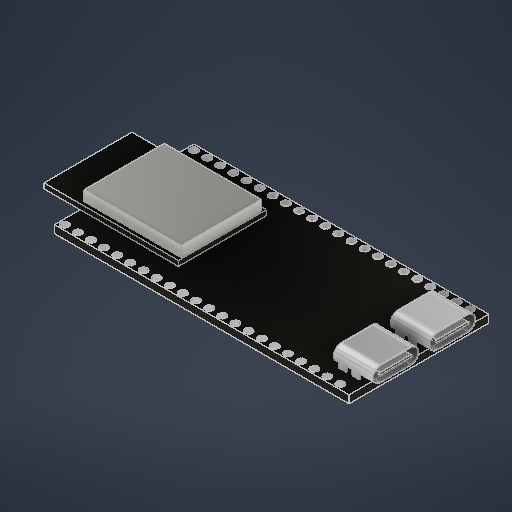
# Autodesk Inventor part: ESP32-S3
Saved by Autodesk Inventor 2027.1 (Build 311270010, 270A)
## iProperties
Created: 2026-09-22
Part Number: ESP32-S3
Material: 열가소성 수지
Document SubType Name: Modeling
Designer: khw
Density: 1.28 g/cm^3
Appearance: 매끄러움 - 검은색
Author: khw
Autodesk Inventor part; units mm, degrees
sketch "스케치1" plane through (0, 0, 0) normal (0, 1, 0) x (-1, 0, 0)
  line L0 (0, 0) -> (57, 0)
  line L1 (57, 0) -> (57, -27)
  line L2 (57, -27) -> (0, -27)
  line L3 (0, -27) -> (0, 0)
  line L4 (63, -5) -> (37, -5)
  line L5 (37, -5) -> (37, -22)
  line L6 (37, -22) -> (63, -22)
  line L7 (63, -22) -> (63, -5)
  point P0 (63, -13.5)
  point P1 (57, -13.5)
  dimension "d0" = 57
  dimension "d1" = 27
  dimension "d2" = 26
  dimension "d3" = 17
  dimension "d4" = 6
  constraints: 16 end point, 4 parallel, 2 horizontal, 2 midpoint, 2 perpendicular, 1 horizontal alignment
  measures "d0" distance of L1.end L2.end
  measures "d1" distance of L0.end L1.end
  measures "d2" distance of L6.end L5.end
  measures "d3" distance of L5.end L4.end
  measures "d4" distance of point (63, -13.5) point (57, -13.5)
extrude "돌출1" add sketch "스케치1" along normal blind 1.5 contours L0 L1 L4 L5 L6 L2 L3 | L1 L6 L5 L4
sketch "스케치2" plane through (0, 1.5, 0) normal (0, 1, 0) x (1, 0, 0)
  line L0 (-38, 5) -> (-64, 5)
  line L1 (-64, 5) -> (-64, 22)
  line L2 (-64, 22) -> (-38, 22)
  line L3 (-38, 22) -> (-38, 5)
  line L4 (-57, 27) -> (-57, 0) projected
  point P0 (0, 0)
  point P1 (-64, 13.5)
  point P2 (-57, 13.5)
  dimension "d7" = 26
  dimension "d8" = 17
  dimension "d9" = 7
  constraints: 8 end point, 2 midpoint, 2 parallel, 1 horizontal, 1 horizontal alignment, 1 perpendicular
  measures "d7" distance of L1.end L2.end
  measures "d8" distance of L0.end L1.end
  measures "d9" distance between parallel lines of L1 L4
extrude "돌출2" add sketch "스케치2" along normal blind 1
sketch "스케치3" plane through (0, 2.5, 0) normal (0, 1, 0) x (1, 0, 0)
  line L0 (-38.2, 5.75) -> (-57, 5.75)
  line L1 (-57, 5.75) -> (-57, 21.25)
  line L2 (-57, 21.25) -> (-38.2, 21.25)
  line L3 (-38.2, 21.25) -> (-38.2, 5.75)
  line L4 (-64, 22) -> (-64, 5) projected
  line L5 (-57, 27) -> (-57, 22) projected
  point P0 (0, 0)
  point P1 (-57, 13.5)
  point P2 (-64, 13.5)
  point P3 (-57, 24.5)
  dimension "d12" = 18.8
  dimension "d13" = 15.5
  constraints: 8 end point, 3 midpoint, 2 parallel, 1 horizontal, 1 horizontal alignment, 1 perpendicular, 1 vertical alignment
  measures "d12" distance of L1.end L2.end
  measures "d13" distance of L0.end L1.end
extrude "돌출3" add sketch "스케치3" along normal blind 2
ref_plane "작업 평면1" through (1, 0, 0) normal (1, 0, 0) x (0, 0, -1)
sketch "스케치4" plane through (1, 0, 0) normal (1, 0, 0) x (0, 0, -1)
  line L0 (0, 0) -> (27, 0) projected
  line L1 (13.5, 0) -> (13.5, 3.5639) construction
  line L2 (5, 3) -> (11, 3) construction
  line L3 (5, 1.5) -> (11, 1.5)
  line L4 (11, 4.5) -> (5, 4.5)
  arc A0 (5, 4.5) -> (5, 1.5) centre (5, 3) ccw
  arc A1 (11, 1.5) -> (11, 4.5) centre (11, 3) ccw
  line L5 (0, 1.5) -> (27, 1.5) projected
  line L6 (5, 3) -> (11, 3) construction
  line L7 (5, 2.75) -> (11, 2.75)
  line L8 (11, 3.25) -> (5, 3.25)
  arc A2 (5, 3.25) -> (5, 2.75) centre (5, 3) ccw
  arc A3 (11, 2.75) -> (11, 3.25) centre (11, 3) ccw
  line L9 (5, 4.4) -> (11, 4.4)
  arc A4 (11, 1.6) -> (11, 4.4) centre (11, 3) ccw
  line L10 (11, 1.6) -> (5, 1.6)
  arc A5 (5, 4.4) -> (5, 1.6) centre (5, 3) ccw
  line L11 (22, 3) -> (16, 3) construction
  line L12 (22, 1.5) -> (16, 1.5)
  line L13 (16, 4.5) -> (22, 4.5)
  arc A6 (22, 1.5) -> (22, 4.5) centre (22, 3) ccw
  arc A7 (16, 4.5) -> (16, 1.5) centre (16, 3) ccw
  line L14 (27, 1.5) -> (0, 1.5)
  line L15 (22, 3) -> (16, 3) construction
  line L16 (22, 2.75) -> (16, 2.75)
  line L17 (16, 3.25) -> (22, 3.25)
  arc A8 (22, 2.75) -> (22, 3.25) centre (22, 3) ccw
  arc A9 (16, 3.25) -> (16, 2.75) centre (16, 3) ccw
  line L18 (22, 4.4) -> (16, 4.4)
  arc A10 (16, 4.4) -> (16, 1.6) centre (16, 3) ccw
  line L19 (16, 1.6) -> (22, 1.6)
  arc A11 (22, 1.6) -> (22, 4.4) centre (22, 3) ccw
  point P0 (8, 3)
  point P1 (12.5, 3)
  point P2 (3.5, 3)
  point P3 (8, 1.5)
  point P4 (8, 3)
  point P5 (19, 3)
  point P6 (14.5, 3)
  point P7 (23.5, 3)
  point P8 (19, 1.5)
  point P9 (19, 3)
  point P10 (16, 1.5)
  point P11 (22, 1.5)
  dimension "d17" = 3
  dimension "d18" = 9
  dimension "d19" = 1
  dimension "d20" = 0.5
  dimension "d21" = 0.1
  constraints: 44 end point, 26 point on circle, 21 symmetric about line, 12 centre point, 8 tangent, 4 equal length, 4 midpoint, 2 point on line, 1 horizontal, 1 vertical, 9 other
  measures "d17" distance between parallel lines of L3 L4
  measures "d18" distance of point (12.5, 3) point (3.5, 3)
  measures "d19" distance from line of point (12.5, 3) L1
  measures "d20" distance between parallel lines of L7 L8
  measures "d21" distance between parallel lines of L4 L9
extrude "돌출4" add sketch "스케치4" against normal blind 7.5
ref_plane "작업 평면2" through (1, 3, -23.5) normal (0, 0, -1) x (-1, 0, 0)
sketch "스케치5" plane through (1, 3, -23.5) normal (0, 0, -1) x (-1, 0, 0)
  line L0 (58, -1.5) -> (1, -1.5) projected
  line L1 (2.5, 0) -> (4, 0)
  line L2 (4, 0) -> (4, -1.5)
  line L3 (4, -1.5) -> (2.5, -1.5)
  line L4 (2.5, -1.5) -> (2.5, 0)
  line L5 (5, 0) -> (6.5, 0)
  line L6 (6.5, 0) -> (6.5, -1.5)
  line L7 (6.5, -1.5) -> (5, -1.5)
  line L8 (5, -1.5) -> (5, 0)
  line L9 (7.5, -1.5) -> (7.5, 1.5) projected
  point P0 (1, -3)
  point P1 (6.5, -0.75)
  point P2 (5, -0.75)
  point P3 (7.5, 0)
  point P4 (2.5, -1.5)
  dimension "d24" = 1.5
  dimension "d25" = 1.5
  dimension "d26" = 1
  dimension "d27" = 1
  constraints: 16 end point, 4 parallel, 3 midpoint, 3 point on line, 2 horizontal, 2 perpendicular, 1 horizontal alignment
  measures "d24" distance of point (6.5, -0.75) point (5, -0.75)
  measures "d25" distance between parallel lines of L4 L2
  measures "d26" distance between parallel lines of L9 L6
  measures "d27" distance between parallel lines of L2 L8
extrude "돌출5" add sketch "스케치5" against normal blind 0.1
ref_plane "작업 평면4" through (1, 3, -19) normal (0, 0, -1) x (-1, 0, 0)
mirror "미러1" about plane through (1, 3, -19) normal (0, 0, -1) of "돌출5"
ref_plane "작업 평면3" through (1, 3, -14.5) normal (0, 0, 1) x (1, 0, 0)
sketch "스케치6" plane through (-6.5, 0, 0) normal (-1, 0, 0) x (0, 0, 1)
  arc A0 (-16, 1.5) -> (-16, 4.5) centre (-16, 3) ccw projected
  line L0 (-16, 1.5) -> (-22, 1.5) projected
  arc A1 (-22, 4.5) -> (-22, 1.5) centre (-22, 3) ccw projected
  line L1 (-22, 4.5) -> (-16, 4.5) projected
  line L2 (-16, 4.4) -> (-22, 4.4) projected
  arc A2 (-22, 4.4) -> (-22, 1.6) centre (-22, 3) ccw projected
  line L3 (-22, 1.6) -> (-16, 1.6) projected
  arc A3 (-16, 1.6) -> (-16, 4.4) centre (-16, 3) ccw projected
  arc A4 (-5, 1.5) -> (-5, 4.5) centre (-5, 3) ccw projected
  line L4 (-5, 1.5) -> (-11, 1.5) projected
  arc A5 (-11, 4.5) -> (-11, 1.5) centre (-11, 3) ccw projected
  line L5 (-11, 4.5) -> (-5, 4.5) projected
  line L6 (-11, 1.6) -> (-5, 1.6) projected
  arc A6 (-5, 1.6) -> (-5, 4.4) centre (-5, 3) ccw projected
  line L7 (-5, 4.4) -> (-11, 4.4) projected
  arc A7 (-11, 4.4) -> (-11, 1.6) centre (-11, 3) ccw projected
  point P0 (0, 0)
extrude "돌출6" add sketch "스케치6" against normal blind 0.1 contours L0 A1 L1 A0 | A3 L3 A2 L2 | L4 A5 L5 A4 | A7 L7 A6 L6
ref_plane "작업 평면5" through (-57, 0, -13.5) normal (0, 0, 1) x (1, 0, 0)
mirror "미러2" about plane through (-57, 0, -13.5) normal (0, 0, 1) of "돌출5", "미러1"
sketch "스케치7" plane through (0, 1.5, 0) normal (0, 1, 0) x (1, 0, 0)
  circle A0 centre (-56, 26) radius 0.5
  circle A1 centre (-56, 26) radius 0.75
  line L0 (0, 27) -> (-57, 27) projected
  line L1 (-57, 27) -> (-57, 22) projected
  point P0 (0, 0)
  dimension "d32" = 1
  dimension "d33" = 1.5
  dimension "d34" = 1
  dimension "d35" = 1
  constraints: 2 centre point, 1 coincident
  measures "d32" diameter of A0
  measures "d33" diameter of A1
  measures "d34" distance from line of A0.centre L0
  measures "d35" distance from line of L1 A0.centre
extrude "돌출7" cut sketch "스케치7" against normal through all contours A0
extrude "돌출8" cut sketch "스케치7" against normal blind 0.05
pattern_sketch "스케치 연계 패턴1" of "돌출7", "돌출8" from (-56, 1.5, -26) copies at (-53.46, 1.5, -26) at (-50.92, 1.5, -26) at (-48.38, 1.5, -26) at (-45.84, 1.5, -26) at (-43.3, 1.5, -26) at (-40.76, 1.5, -26) at (-38.22, 1.5, -26) at (-35.68, 1.5, -26) at (-33.14, 1.5, -26) at (-30.6, 1.5, -26) at (-28.06, 1.5, -26) at (-25.52, 1.5, -26) at (-22.98, 1.5, -26) at (-20.44, 1.5, -26) at (-17.9, 1.5, -26) at (-15.36, 1.5, -26) at (-12.82, 1.5, -26) at (-10.28, 1.5, -26) at (-7.74, 1.5, -26) at (-5.2, 1.5, -26) at (-2.66, 1.5, -26)
mirror "미러3" about plane through (-57, 0, -13.5) normal (0, 0, 1) of "돌출7", "돌출8", "스케치 연계 패턴1"
ref_plane "작업 평면6" through (1, 3, -8) normal (0, 0, -1) x (-1, 0, 0)
sketch "스케치8" plane through (0, 1.5, 0) normal (0, 1, 0) x (1, 0, 0)
  circle A0 centre (-56, 26) radius 0.75 projected
  line L0 (-4, 12.5) -> (-4, 12.4) projected
  line L1 (-4, 12.4) -> (-5.5, 12.4) projected
  line L2 (-5.5, 12.4) -> (-5.5, 12.5) projected
  line L3 (-5.5, 12.5) -> (-4, 12.5) projected
  line L4 (-1.5, 12.5) -> (-1.5, 12.4) projected
  line L5 (-1.5, 12.4) -> (-3, 12.4) projected
  line L6 (-3, 12.4) -> (-3, 12.5) projected
  line L7 (-3, 12.5) -> (-1.5, 12.5) projected
  line L8 (-4, 3.6) -> (-4, 3.5) projected
  line L9 (-4, 3.5) -> (-5.5, 3.5) projected
  line L10 (-5.5, 3.5) -> (-5.5, 3.6) projected
  line L11 (-5.5, 3.6) -> (-4, 3.6) projected
  line L12 (-1.5, 3.6) -> (-1.5, 3.5) projected
  line L13 (-1.5, 3.5) -> (-3, 3.5) projected
  line L14 (-3, 3.5) -> (-3, 3.6) projected
  line L15 (-3, 3.6) -> (-1.5, 3.6) projected
  line L16 (-4, 14.6) -> (-4, 14.5) projected
  line L17 (-4, 14.5) -> (-5.5, 14.5) projected
  line L18 (-5.5, 14.5) -> (-5.5, 14.6) projected
  line L19 (-5.5, 14.6) -> (-4, 14.6) projected
  line L20 (-1.5, 14.6) -> (-1.5, 14.5) projected
  line L21 (-1.5, 14.5) -> (-3, 14.5) projected
  line L22 (-3, 14.5) -> (-3, 14.6) projected
  line L23 (-3, 14.6) -> (-1.5, 14.6) projected
  line L24 (-4, 23.5) -> (-4, 23.4) projected
  line L25 (-4, 23.4) -> (-5.5, 23.4) projected
  line L26 (-5.5, 23.4) -> (-5.5, 23.5) projected
  line L27 (-5.5, 23.5) -> (-4, 23.5) projected
  line L28 (-1.5, 23.5) -> (-1.5, 23.4) projected
  line L29 (-1.5, 23.4) -> (-3, 23.4) projected
  line L30 (-3, 23.4) -> (-3, 23.5) projected
  line L31 (-3, 23.5) -> (-1.5, 23.5) projected
  line L32 (0, 16) -> (-6.5, 16) projected
  line L33 (-6.5, 16) -> (-6.5, 22) projected
  line L34 (0, 22) -> (-6.5, 22) projected
  line L35 (0, 22) -> (0, 27) projected
  line L36 (0, 27) -> (-57, 27) projected
  line L37 (-57, 27) -> (-57, 22) projected
  line L38 (-57, 22) -> (-38, 22) projected
  line L39 (-38, 22) -> (-38, 5) projected
  line L40 (-38, 5) -> (-57, 5) projected
  line L41 (-57, 5) -> (-57, 0) projected
  line L42 (-57, 0) -> (0, 0) projected
  line L43 (0, 0) -> (0, 5) projected
  line L44 (0, 5) -> (-6.5, 5) projected
  line L45 (-6.5, 5) -> (-6.5, 11) projected
  line L46 (0, 11) -> (-6.5, 11) projected
  line L47 (0, 11) -> (0, 16) projected
  point P0 (-53.46, 26)
  point P1 (-50.92, 26)
  point P2 (-48.38, 26)
  point P3 (-45.84, 26)
  point P4 (-43.3, 26)
  point P5 (-40.76, 26)
  point P6 (-38.22, 26)
  point P7 (-35.68, 26)
  point P8 (-33.14, 26)
  point P9 (-30.6, 26)
  point P10 (-28.06, 26)
  point P11 (-25.52, 26)
  point P12 (-22.98, 26)
  point P13 (-20.44, 26)
  point P14 (-17.9, 26)
  point P15 (-15.36, 26)
  point P16 (-12.82, 26)
  point P17 (-10.28, 26)
  point P18 (-7.74, 26)
  point P19 (-5.2, 26)
  point P20 (-2.66, 26)
  dimension "d42" = 2.54
  constraints: 1 coincident, 1 horizontal, 21 other
  measures "d42" distance of point (-56, 26) point (-53.46, 26)
